Autodesk Fusion 360 part; units mm, degrees
(part 6 of 7)
sketch "Join stock profile (1) (6)" plane through (0, 0, 33.1) normal (0, 0, 1) x (1, 0, 0) in component "rear left public turning fork"
  line L0 (-286, 258) -> (-279, 258)
  line L1 (-279, 258) -> (-279, 272)
  line L2 (-279, 272) -> (-286, 272)
  line L3 (-286, 272) -> (-286, 258)
extrude "Join 3'''''" add sketch "Join stock profile (1) (6)" along normal blind 39 bodies 228 in component "rear left public turning fork"
ref_plane "WorkPlane4" through (0, 0, 33.1) normal (0, 0, 1) x (1, 0, 0) in component "rear left public turning fork"
sketch "Join stock profile (2) (7)" plane through (0, 0, 33.1) normal (0, 0, 1) x (1, 0, 0) in component "rear left public turning fork"
  line L0 (-251, 258) -> (-244, 258)
  line L1 (-244, 258) -> (-244, 272)
  line L2 (-244, 272) -> (-251, 272)
  line L3 (-251, 272) -> (-251, 258)
extrude "Join 4'''''" add sketch "Join stock profile (2) (7)" along normal blind 39 bodies 228 in component "rear left public turning fork"
ref_plane "WorkPlane5" through (-287, 0, 0) normal (1, 0, 0) x (0, 1, 0) in component "rear left public turning fork"
sketch "Cut stock profile (62)" plane through (-287, 0, 0) normal (1, 0, 0) x (0, 0, -1) in component "rear left public turning fork"
  circle A0 centre (-38.1, 265) radius 5
ref_plane "WorkPlane1" through (-286, 0, 0) normal (1, 0, 0) x (0, 1, 0) in component "rear left public wheel axle"
sketch "New stock profile (103)" plane through (-286, 0, 0) normal (1, 0, 0) x (0, 0, -1) in component "rear left public wheel axle"
  circle A0 centre (-38.1, 265) radius 5
extrude "New 1''''''''''''''''''''''''''''''''''''''''''''''''''''''''''''''''''''''''''''''''''''''''''''''''''''''" add sketch "New stock profile (103)" along normal blind 42 separate body makes body 229 in component "rear left public wheel axle"
ref_plane "WorkPlane1" through (10, 0, 0) normal (1, 0, 0) x (0, 1, 0) in component "rear left public wheel"
sketch "New stock profile (104)" plane through (10, 0, 0) normal (1, 0, 0) x (0, 0, -1) in component "rear left public wheel"
  circle A0 centre (-10, 0) radius 38.1
  circle A1 centre (-10, 0) radius 5
extrude "New 1'''''''''''''''''''''''''''''''''''''''''''''''''''''''''''''''''''''''''''''''''''''''''''''''''''''''" add sketch "New stock profile (104)" against normal blind 26 separate body makes body 230 in component "rear left public wheel"
ref_plane "WorkPlane1" through (0, 0, 3.1) normal (0, 0, 1) x (1, 0, 0) in component "rear right public drive housing"
sketch "New stock profile (105)" plane through (0, 0, 3.1) normal (0, 0, 1) x (1, 0, 0) in component "rear right public drive housing"
  circle A0 centre (3, 3) radius 30
  circle A1 centre (3, 3) radius 20
extrude "New 1''''''''''''''''''''''''''''''''''''''''''''''''''''''''''''''''''''''''''''''''''''''''''''''''''''''''" add sketch "New stock profile (105)" along normal blind 48 separate body makes body 231 in component "rear right public drive housing"
ref_plane "WorkPlane2" through (0, 0, -1.9) normal (0, 0, 1) x (1, 0, 0) in component "rear right public drive housing"
sketch "Join stock profile (39)" plane through (0, 0, -1.9) normal (0, 0, 1) x (1, 0, 0) in component "rear right public drive housing"
  line L0 (15, 15) -> (29, 15)
  line L1 (29, 15) -> (29, 29)
  line L2 (29, 29) -> (15, 29)
  line L3 (15, 29) -> (15, 15)
extrude "Join 2''''''''''''''''''''''''''''''''''''''" add sketch "Join stock profile (39)" along normal blind 53 bodies 231 in component "rear right public drive housing"
ref_plane "WorkPlane3" through (0, 0, -4.4362) normal (0, 0, 1) x (1, 0, 0) in component "rear right public drive housing"
sketch "Join stock profile (1) (7)" plane through (0, 0, -4.4362) normal (0, 0, 1) x (1, 0, 0) in component "rear right public drive housing"
  line L0 (22, -33) -> (29, -33)
  line L1 (29, -33) -> (29, 28)
  line L2 (29, 28) -> (22, 28)
  line L3 (22, 28) -> (22, -33)
extrude "Join 3''''''" add sketch "Join stock profile (1) (7)" along normal blind 4.2863 bodies 231 in component "rear right public drive housing"
ref_plane "WorkPlane4" through (0, 0, -4.4362) normal (0, 0, 1) x (1, 0, 0) in component "rear right public drive housing"
sketch "Join stock profile (2) (8)" plane through (0, 0, -4.4362) normal (0, 0, 1) x (1, 0, 0) in component "rear right public drive housing"
  line L0 (25, -34) -> (90.7, -34)
  line L1 (90.7, -34) -> (90.7, -23)
  line L2 (90.7, -23) -> (25, -23)
  line L3 (25, -23) -> (25, -34)
extrude "Join 4''''''" add sketch "Join stock profile (2) (8)" along normal blind 4.2863 bodies 231 in component "rear right public drive housing"
ref_plane "WorkPlane5" through (0, 0, -4.4362) normal (0, 0, 1) x (1, 0, 0) in component "rear right public drive housing"
sketch "Join stock profile (3) (5)" plane through (0, 0, -4.4362) normal (0, 0, 1) x (1, 0, 0) in component "rear right public drive housing"
  line L0 (-33, 22) -> (28, 22)
  line L1 (28, 22) -> (28, 29)
  line L2 (28, 29) -> (-33, 29)
  line L3 (-33, 29) -> (-33, 22)
extrude "Join 5'''" add sketch "Join stock profile (3) (5)" along normal blind 4.2863 bodies 231 in component "rear right public drive housing"
ref_plane "WorkPlane6" through (0, 0, -4.4362) normal (0, 0, 1) x (1, 0, 0) in component "rear right public drive housing"
sketch "Join stock profile (4) (5)" plane through (0, 0, -4.4362) normal (0, 0, 1) x (1, 0, 0) in component "rear right public drive housing"
  line L0 (-34, 25) -> (-23, 25)
  line L1 (-23, 25) -> (-23, 90.7)
  line L2 (-23, 90.7) -> (-34, 90.7)
  line L3 (-34, 90.7) -> (-34, 25)
extrude "Join 6'''" add sketch "Join stock profile (4) (5)" along normal blind 4.2863 bodies 231 in component "rear right public drive housing"
ref_plane "WorkPlane7" through (0, 0, -4.4463) normal (0, 0, 1) x (1, 0, 0) in component "rear right public drive housing"
sketch "Cut stock profile (63)" plane through (0, 0, -4.4463) normal (0, 0, 1) x (1, 0, 0) in component "rear right public drive housing"
  circle A0 centre (60.15, -28.75) radius 2.5
extrude "Cut 7''''''''" cut sketch "Cut stock profile (63)" along normal blind 4.3063 bodies 231 in component "rear right public drive housing"
extrude "Extrude4''''''''''''''" [no effect] in component "rear right tab 1-1 socket screw"
ref_plane "WorkPlane8" through (0, 0, -4.4463) normal (0, 0, 1) x (1, 0, 0) in component "rear right public drive housing"
sketch "Cut stock profile (1) (17)" plane through (0, 0, -4.4463) normal (0, 0, 1) x (1, 0, 0) in component "rear right public drive housing"
  circle A0 centre (85.55, -28.75) radius 2.5
extrude "Cut 8'''" cut sketch "Cut stock profile (1) (17)" along normal blind 4.3063 bodies 231 in component "rear right public drive housing"
extrude "Extrude4'''''''''''''''" [no effect] in component "rear right tab 1-2 socket screw"
ref_plane "WorkPlane9" through (0, 0, -4.4463) normal (0, 0, 1) x (1, 0, 0) in component "rear right public drive housing"
sketch "Cut stock profile (2) (17)" plane through (0, 0, -4.4463) normal (0, 0, 1) x (1, 0, 0) in component "rear right public drive housing"
  circle A0 centre (-28.75, 60.15) radius 2.5
extrude "Cut 9'''" cut sketch "Cut stock profile (2) (17)" along normal blind 4.3063 bodies 231 in component "rear right public drive housing"
extrude "Extrude4''''''''''''''''" [no effect] in component "rear right tab 2-1 socket screw"
ref_plane "WorkPlane10" through (0, 0, -4.4463) normal (0, 0, 1) x (1, 0, 0) in component "rear right public drive housing"
sketch "Cut stock profile (3) (15)" plane through (0, 0, -4.4463) normal (0, 0, 1) x (1, 0, 0) in component "rear right public drive housing"
  circle A0 centre (-28.75, 85.55) radius 2.5
extrude "Cut 10'''" cut sketch "Cut stock profile (3) (15)" along normal blind 4.3063 bodies 231 in component "rear right public drive housing"
extrude "Extrude4'''''''''''''''''" [no effect] in component "rear right tab 2-2 socket screw"
ref_plane "WorkPlane11" through (0, 0, 50.65) normal (0, 0, 1) x (1, 0, 0) in component "rear right public drive housing"
sketch "Join stock profile (5) (5)" plane through (0, 0, 50.65) normal (0, 0, 1) x (1, 0, 0) in component "rear right public drive housing"
  line L0 (22, -33) -> (29, -33)
  line L1 (29, -33) -> (29, 28)
  line L2 (29, 28) -> (22, 28)
  line L3 (22, 28) -> (22, -33)
extrude "Join 11'''" add sketch "Join stock profile (5) (5)" along normal blind 3.6625 bodies 231 in component "rear right public drive housing"
ref_plane "WorkPlane12" through (0, 0, 50.65) normal (0, 0, 1) x (1, 0, 0) in component "rear right public drive housing"
sketch "Join stock profile (6) (5)" plane through (0, 0, 50.65) normal (0, 0, 1) x (1, 0, 0) in component "rear right public drive housing"
  line L0 (25, -34) -> (90.7, -34)
  line L1 (90.7, -34) -> (90.7, -23)
  line L2 (90.7, -23) -> (25, -23)
  line L3 (25, -23) -> (25, -34)
extrude "Join 12'''" add sketch "Join stock profile (6) (5)" along normal blind 3.6625 bodies 231 in component "rear right public drive housing"
ref_plane "WorkPlane13" through (0, 0, 50.65) normal (0, 0, 1) x (1, 0, 0) in component "rear right public drive housing"
sketch "Join stock profile (7) (5)" plane through (0, 0, 50.65) normal (0, 0, 1) x (1, 0, 0) in component "rear right public drive housing"
  line L0 (-33, 22) -> (28, 22)
  line L1 (28, 22) -> (28, 29)
  line L2 (28, 29) -> (-33, 29)
  line L3 (-33, 29) -> (-33, 22)
extrude "Join 13'''" add sketch "Join stock profile (7) (5)" along normal blind 3.6625 bodies 231 in component "rear right public drive housing"
ref_plane "WorkPlane14" through (0, 0, 50.65) normal (0, 0, 1) x (1, 0, 0) in component "rear right public drive housing"
sketch "Join stock profile (8) (5)" plane through (0, 0, 50.65) normal (0, 0, 1) x (1, 0, 0) in component "rear right public drive housing"
  line L0 (-34, 25) -> (-23, 25)
  line L1 (-23, 25) -> (-23, 90.7)
  line L2 (-23, 90.7) -> (-34, 90.7)
  line L3 (-34, 90.7) -> (-34, 25)
extrude "Join 14'''" add sketch "Join stock profile (8) (5)" along normal blind 3.6625 bodies 231 in component "rear right public drive housing"
ref_plane "WorkPlane15" through (0, 0, 50.64) normal (0, 0, 1) x (1, 0, 0) in component "rear right public drive housing"
sketch "Cut stock profile (4) (15)" plane through (0, 0, 50.64) normal (0, 0, 1) x (1, 0, 0) in component "rear right public drive housing"
  circle A0 centre (60.15, -28.75) radius 2.5
extrude "Cut 15'''" cut sketch "Cut stock profile (4) (15)" along normal blind 3.6825 bodies 231 in component "rear right public drive housing"
extrude "Extrude5''''''''''''''" [no effect] in component "rear right tab 1-1 socket screw"
extrude "Extrude2'''''''''''''''" [no effect] in component "rear right tab 1-1 locknut"
ref_plane "WorkPlane16" through (0, 0, 50.64) normal (0, 0, 1) x (1, 0, 0) in component "rear right public drive housing"
sketch "Cut stock profile (5) (13)" plane through (0, 0, 50.64) normal (0, 0, 1) x (1, 0, 0) in component "rear right public drive housing"
  circle A0 centre (85.55, -28.75) radius 2.5
extrude "Cut 16'''" cut sketch "Cut stock profile (5) (13)" along normal blind 3.6825 bodies 231 in component "rear right public drive housing"
extrude "Extrude5'''''''''''''''" [no effect] in component "rear right tab 1-2 socket screw"
extrude "Extrude2''''''''''''''''" [no effect] in component "rear right tab 1-2 locknut"
ref_plane "WorkPlane17" through (0, 0, 50.64) normal (0, 0, 1) x (1, 0, 0) in component "rear right public drive housing"
sketch "Cut stock profile (6) (5)" plane through (0, 0, 50.64) normal (0, 0, 1) x (1, 0, 0) in component "rear right public drive housing"
  circle A0 centre (-28.75, 60.15) radius 2.5
extrude "Cut 17'''" cut sketch "Cut stock profile (6) (5)" along normal blind 3.6825 bodies 231 in component "rear right public drive housing"
extrude "Extrude5''''''''''''''''" [no effect] in component "rear right tab 2-1 socket screw"
extrude "Extrude2'''''''''''''''''" [no effect] in component "rear right tab 2-1 locknut"
ref_plane "WorkPlane18" through (0, 0, 50.64) normal (0, 0, 1) x (1, 0, 0) in component "rear right public drive housing"
sketch "Cut stock profile (7) (5)" plane through (0, 0, 50.64) normal (0, 0, 1) x (1, 0, 0) in component "rear right public drive housing"
  circle A0 centre (-28.75, 85.55) radius 2.5
extrude "Cut 18'''" cut sketch "Cut stock profile (7) (5)" along normal blind 3.6825 bodies 231 in component "rear right public drive housing"
extrude "Extrude5'''''''''''''''''" [no effect] in component "rear right tab 2-2 socket screw"
extrude "Extrude2''''''''''''''''''" [no effect] in component "rear right tab 2-2 locknut"
ref_plane "WorkPlane1" through (0, 0, 6.1) normal (0, 0, 1) x (1, 0, 0) in component "rear right public motor reserve"
sketch "New stock profile (106)" plane through (0, 0, 6.1) normal (0, 0, 1) x (1, 0, 0) in component "rear right public motor reserve"
  circle A0 centre (19, 19) radius 19
extrude "New 1'''''''''''''''''''''''''''''''''''''''''''''''''''''''''''''''''''''''''''''''''''''''''''''''''''''''''" add sketch "New stock profile (106)" along normal blind 50.36 separate body makes body 232 in component "rear right public motor reserve"
ref_plane "WorkPlane1" through (0, 0, 68.1) normal (0, 0, 1) x (1, 0, 0) in component "rear right public turning fork"
sketch "New stock profile (107)" plane through (0, 0, 68.1) normal (0, 0, 1) x (1, 0, 0) in component "rear right public turning fork"
  circle A0 centre (-265, -265) radius 19.95
extrude "New 1''''''''''''''''''''''''''''''''''''''''''''''''''''''''''''''''''''''''''''''''''''''''''''''''''''''''''" add sketch "New stock profile (107)" along normal blind 23 separate body makes body 233 in component "rear right public turning fork"
ref_plane "WorkPlane2" through (0, 0, 68.1) normal (0, 0, 1) x (1, 0, 0) in component "rear right public turning fork"
sketch "Join stock profile (40)" plane through (0, 0, 68.1) normal (0, 0, 1) x (1, 0, 0) in component "rear right public turning fork"
  circle A0 centre (-265, -265) radius 25.5
extrude "Join 2'''''''''''''''''''''''''''''''''''''''" add sketch "Join stock profile (40)" along normal blind 5 bodies 233 in component "rear right public turning fork"
ref_plane "WorkPlane3" through (0, 0, 33.1) normal (0, 0, 1) x (1, 0, 0) in component "rear right public turning fork"
sketch "Join stock profile (1) (8)" plane through (0, 0, 33.1) normal (0, 0, 1) x (1, 0, 0) in component "rear right public turning fork"
  line L0 (-272, -286) -> (-258, -286)
  line L1 (-258, -286) -> (-258, -279)
  line L2 (-258, -279) -> (-272, -279)
  line L3 (-272, -279) -> (-272, -286)
extrude "Join 3'''''''" add sketch "Join stock profile (1) (8)" along normal blind 39 bodies 233 in component "rear right public turning fork"
ref_plane "WorkPlane4" through (0, 0, 33.1) normal (0, 0, 1) x (1, 0, 0) in component "rear right public turning fork"
sketch "Join stock profile (2) (9)" plane through (0, 0, 33.1) normal (0, 0, 1) x (1, 0, 0) in component "rear right public turning fork"
  line L0 (-272, -251) -> (-258, -251)
  line L1 (-258, -251) -> (-258, -244)
  line L2 (-258, -244) -> (-272, -244)
  line L3 (-272, -244) -> (-272, -251)
extrude "Join 4'''''''" add sketch "Join stock profile (2) (9)" along normal blind 39 bodies 233 in component "rear right public turning fork"
ref_plane "WorkPlane5" through (0, -287, 0) normal (0, 1, 0) x (0, 0, 1) in component "rear right public turning fork"
sketch "Cut stock profile (64)" plane through (0, -287, 0) normal (0, 1, 0) x (1, 0, 0) in component "rear right public turning fork"
  circle A0 centre (-265, -38.1) radius 5
ref_plane "WorkPlane1" through (0, -286, 0) normal (0, 1, 0) x (0, 0, 1) in component "rear right public wheel axle"
sketch "New stock profile (108)" plane through (0, -286, 0) normal (0, 1, 0) x (1, 0, 0) in component "rear right public wheel axle"
  circle A0 centre (-265, -38.1) radius 5
extrude "New 1'''''''''''''''''''''''''''''''''''''''''''''''''''''''''''''''''''''''''''''''''''''''''''''''''''''''''''" add sketch "New stock profile (108)" along normal blind 42 separate body makes body 234 in component "rear right public wheel axle"
ref_plane "WorkPlane1" through (0, 0, 3) normal (0, 0, 1) x (1, 0, 0) in component "rear right public wheel"
sketch "New stock profile (109)" plane through (0, 0, 3) normal (0, 0, 1) x (1, 0, 0) in component "rear right public wheel"
  circle A0 centre (-3, 0) radius 38.1
  circle A1 centre (-3, 0) radius 5
extrude "New 1''''''''''''''''''''''''''''''''''''''''''''''''''''''''''''''''''''''''''''''''''''''''''''''''''''''''''''" add sketch "New stock profile (109)" along normal blind 26 separate body makes body 235 in component "rear right public wheel"
ref_plane "WorkPlane1" through (0, 0, 38.1) normal (0, 0, 1) x (1, 0, 0)
sketch "Module joint datum" plane through (0, 0, 38.1) normal (0, 0, 1) x (1, 0, 0)
  point P0 (265, 265)
ref_plane "WorkPlane2" through (0, 0, 38.1) normal (0, 0, 1) x (1, 0, 0)
sketch "Module joint datum (1)" plane through (0, 0, 38.1) normal (0, 0, 1) x (1, 0, 0)
  point P0 (265, -265)
ref_plane "WorkPlane3" through (0, 0, 38.1) normal (0, 0, 1) x (1, 0, 0)
sketch "Module joint datum (2)" plane through (0, 0, 38.1) normal (0, 0, 1) x (1, 0, 0)
  point P0 (-265, 265)
ref_plane "WorkPlane4" through (0, 0, 38.1) normal (0, 0, 1) x (1, 0, 0)
sketch "Module joint datum (3)" plane through (0, 0, 38.1) normal (0, 0, 1) x (1, 0, 0)
  point P0 (-265, -265)
ref_plane "WorkPlane7" through (0, -22.225, 0) normal (0, 1, 0) x (0, 0, 1) in component "rear perimeter tube"
sketch "Cut stock profile (5) (14)" plane through (0, -22.225, 0) normal (0, 1, 0) x (1, 0, 0) in component "rear perimeter tube"
  line L0 (9.525, 1) -> (-9.525, 1)
  line L1 (-9.525, 1) -> (-9.525, -630.2)
  line L2 (-9.525, -630.2) -> (9.525, -630.2)
  line L3 (9.525, -630.2) -> (9.525, 1)
extrude "Cut 1" cut sketch "Cut stock profile (5) (14)" along normal blind 44.45 bodies 127 in component "rear perimeter tube"
ref_plane "WorkPlane8" through (-9.2, 0, 0) normal (1, 0, 0) x (0, 1, 0) in component "rear perimeter tube"
sketch "Cut stock profile (6) (6)" plane through (-9.2, 0, 0) normal (1, 0, 0) x (0, 0, -1) in component "rear perimeter tube"
  circle A0 centre (-509.75, -5.3) radius 6.55
extrude "Cut 1 (1)" cut sketch "Cut stock profile (6) (6)" against normal blind 4.5 bodies 127 in component "rear perimeter tube"
ref_plane "WorkPlane9" through (-9.2, 0, 0) normal (1, 0, 0) x (0, 1, 0) in component "rear perimeter tube"
sketch "Cut stock profile (7) (6)" plane through (-9.2, 0, 0) normal (1, 0, 0) x (0, 0, -1) in component "rear perimeter tube"
  circle A0 centre (-509.75, 15.7) radius 6.55
extrude "Cut 1 (2)" cut sketch "Cut stock profile (7) (6)" against normal blind 4.5 bodies 127 in component "rear perimeter tube"
ref_plane "WorkPlane10" through (-9.2, 0, 0) normal (1, 0, 0) x (0, 1, 0) in component "rear perimeter tube"
sketch "Cut stock profile (8) (2)" plane through (-9.2, 0, 0) normal (1, 0, 0) x (0, 0, -1) in component "rear perimeter tube"
  circle A0 centre (-119.45, -5.3) radius 6.55
extrude "Cut 1 (3)" cut sketch "Cut stock profile (8) (2)" against normal blind 4.5 bodies 127 in component "rear perimeter tube"
ref_plane "WorkPlane11" through (-9.2, 0, 0) normal (1, 0, 0) x (0, 1, 0) in component "rear perimeter tube"
sketch "Cut stock profile (9) (2)" plane through (-9.2, 0, 0) normal (1, 0, 0) x (0, 0, -1) in component "rear perimeter tube"
  circle A0 centre (-119.45, 15.7) radius 6.55
extrude "Cut 1 (4)" cut sketch "Cut stock profile (9) (2)" against normal blind 4.5 bodies 127 in component "rear perimeter tube"
ref_plane "WorkPlane7" through (9.2, 0, 0) normal (1, 0, 0) x (0, 1, 0) in component "right perimeter tube"
sketch "Cut stock profile (5) (15)" plane through (9.2, 0, 0) normal (1, 0, 0) x (0, 0, -1) in component "right perimeter tube"
  circle A0 centre (-535.15, -5.3) radius 6.55
extrude "Cut 1'" cut sketch "Cut stock profile (5) (15)" along normal blind 4.5 bodies 128 in component "right perimeter tube"
ref_plane "WorkPlane8" through (9.2, 0, 0) normal (1, 0, 0) x (0, 1, 0) in component "right perimeter tube"
sketch "Cut stock profile (6) (7)" plane through (9.2, 0, 0) normal (1, 0, 0) x (0, 0, -1) in component "right perimeter tube"
  circle A0 centre (-535.15, 15.7) radius 6.55
extrude "Cut 1 (1)'" cut sketch "Cut stock profile (6) (7)" along normal blind 4.5 bodies 128 in component "right perimeter tube"
ref_plane "WorkPlane9" through (9.2, 0, 0) normal (1, 0, 0) x (0, 1, 0) in component "right perimeter tube"
sketch "Cut stock profile (7) (7)" plane through (9.2, 0, 0) normal (1, 0, 0) x (0, 0, -1) in component "right perimeter tube"
  circle A0 centre (-144.85, -5.3) radius 6.55
extrude "Cut 1 (2)'" cut sketch "Cut stock profile (7) (7)" along normal blind 4.5 bodies 128 in component "right perimeter tube"
ref_plane "WorkPlane10" through (9.2, 0, 0) normal (1, 0, 0) x (0, 1, 0) in component "right perimeter tube"
sketch "Cut stock profile (8) (3)" plane through (9.2, 0, 0) normal (1, 0, 0) x (0, 0, -1) in component "right perimeter tube"
  circle A0 centre (-144.85, 15.7) radius 6.55
extrude "Cut 1 (3)'" cut sketch "Cut stock profile (8) (3)" along normal blind 4.5 bodies 128 in component "right perimeter tube"
ref_plane "WorkPlane5" through (9.2, 0, 0) normal (1, 0, 0) x (0, 1, 0) in component "right front return"
sketch "Cut stock profile (3) (16)" plane through (9.2, 0, 0) normal (1, 0, 0) x (0, 0, -1) in component "right front return"
  circle A0 centre (-119.45, -5.3) radius 6.55
extrude "Cut 1''" cut sketch "Cut stock profile (3) (16)" along normal blind 4.5 bodies 129 in component "right front return"
ref_plane "WorkPlane6" through (9.2, 0, 0) normal (1, 0, 0) x (0, 1, 0) in component "right front return"
sketch "Cut stock profile (4) (16)" plane through (9.2, 0, 0) normal (1, 0, 0) x (0, 0, -1) in component "right front return"
  circle A0 centre (-119.45, 15.7) radius 6.55
extrude "Cut 1 (1)''" cut sketch "Cut stock profile (4) (16)" along normal blind 4.5 bodies 129 in component "right front return"
ref_plane "WorkPlane3" through (0, -14.4752, 0) normal (0, 1, 0) x (0, 0, 1) in component "right floor sill"
sketch "Cut stock profile (1) (18)" plane through (0, -14.4752, 0) normal (0, 1, 0) x (1, 0, 0) in component "right floor sill"
  line L0 (4.0498, 1) -> (4.0498, -481)
  line L1 (4.0498, -481) -> (19.9502, -481)
  line L2 (19.9502, -481) -> (19.9502, 1)
  line L3 (19.9502, 1) -> (4.0498, 1)
extrude "Cut 1'''" cut sketch "Cut stock profile (1) (18)" along normal blind 15.9004 bodies 130 in component "right floor sill"
ref_plane "WorkPlane7" through (-9.2, 0, 0) normal (1, 0, 0) x (0, 1, 0) in component "left perimeter tube"
sketch "Cut stock profile (5) (16)" plane through (-9.2, 0, 0) normal (1, 0, 0) x (0, 0, -1) in component "left perimeter tube"
  circle A0 centre (-535.15, -5.3) radius 6.55
extrude "Cut 1''''" cut sketch "Cut stock profile (5) (16)" against normal blind 4.5 bodies 133 in component "left perimeter tube"
ref_plane "WorkPlane8" through (-9.2, 0, 0) normal (1, 0, 0) x (0, 1, 0) in component "left perimeter tube"
sketch "Cut stock profile (6) (8)" plane through (-9.2, 0, 0) normal (1, 0, 0) x (0, 0, -1) in component "left perimeter tube"
  circle A0 centre (-535.15, 15.7) radius 6.55
extrude "Cut 1 (1)'''" cut sketch "Cut stock profile (6) (8)" against normal blind 4.5 bodies 133 in component "left perimeter tube"
ref_plane "WorkPlane9" through (-9.2, 0, 0) normal (1, 0, 0) x (0, 1, 0) in component "left perimeter tube"
sketch "Cut stock profile (7) (8)" plane through (-9.2, 0, 0) normal (1, 0, 0) x (0, 0, -1) in component "left perimeter tube"
  circle A0 centre (-144.85, -5.3) radius 6.55
extrude "Cut 1 (2)''" cut sketch "Cut stock profile (7) (8)" against normal blind 4.5 bodies 133 in component "left perimeter tube"
ref_plane "WorkPlane10" through (-9.2, 0, 0) normal (1, 0, 0) x (0, 1, 0) in component "left perimeter tube"
sketch "Cut stock profile (8) (4)" plane through (-9.2, 0, 0) normal (1, 0, 0) x (0, 0, -1) in component "left perimeter tube"
  circle A0 centre (-144.85, 15.7) radius 6.55
extrude "Cut 1 (3)''" cut sketch "Cut stock profile (8) (4)" against normal blind 4.5 bodies 133 in component "left perimeter tube"
ref_plane "WorkPlane5" through (9.2, 0, 0) normal (1, 0, 0) x (0, 1, 0) in component "left front return"
sketch "Cut stock profile (3) (17)" plane through (9.2, 0, 0) normal (1, 0, 0) x (0, 0, -1) in component "left front return"
  circle A0 centre (-45.15, -5.3) radius 6.55
extrude "Cut 1'''''" cut sketch "Cut stock profile (3) (17)" along normal blind 4.5 bodies 134 in component "left front return"
ref_plane "WorkPlane6" through (9.2, 0, 0) normal (1, 0, 0) x (0, 1, 0) in component "left front return"
sketch "Cut stock profile (4) (17)" plane through (9.2, 0, 0) normal (1, 0, 0) x (0, 0, -1) in component "left front return"
  circle A0 centre (-45.15, 15.7) radius 6.55
extrude "Cut 1 (1)''''" cut sketch "Cut stock profile (4) (17)" along normal blind 4.5 bodies 134 in component "left front return"
ref_plane "WorkPlane3" through (0, -14.4752, 0) normal (0, 1, 0) x (0, 0, 1) in component "left floor sill"
sketch "Cut stock profile (1) (19)" plane through (0, -14.4752, 0) normal (0, 1, 0) x (1, 0, 0) in component "left floor sill"
  line L0 (-19.9502, 1) -> (-19.9502, -481)
  line L1 (-19.9502, -481) -> (-4.0498, -481)
  line L2 (-4.0498, -481) -> (-4.0498, 1)
  line L3 (-4.0498, 1) -> (-19.9502, 1)
extrude "Cut 1''''''" cut sketch "Cut stock profile (1) (19)" along normal blind 15.9004 bodies 135 in component "left floor sill"
ref_plane "WorkPlane6" through (0, 287, 0) normal (0, 1, 0) x (0, 0, 1) in component "front left public turning fork"
sketch "Cut stock profile (1) (20)" plane through (0, 287, 0) normal (0, 1, 0) x (1, 0, 0) in component "front left public turning fork"
  circle A0 centre (265, -38.1) radius 5
extrude "Cut 1'''''''" cut sketch "Cut stock profile (1) (20)" against normal blind 44 bodies 218 in component "front left public turning fork"
ref_plane "WorkPlane6" through (287, 0, 0) normal (1, 0, 0) x (0, 1, 0) in component "front right public turning fork"
sketch "Cut stock profile (1) (21)" plane through (287, 0, 0) normal (1, 0, 0) x (0, 0, -1) in component "front right public turning fork"
  circle A0 centre (-38.1, -265) radius 5
extrude "Cut 1''''''''" cut sketch "Cut stock profile (1) (21)" against normal blind 44 bodies 223 in component "front right public turning fork"
ref_plane "WorkPlane6" through (-287, 0, 0) normal (1, 0, 0) x (0, 1, 0) in component "rear left public turning fork"
sketch "Cut stock profile (1) (22)" plane through (-287, 0, 0) normal (1, 0, 0) x (0, 0, -1) in component "rear left public turning fork"
  circle A0 centre (-38.1, 265) radius 5
extrude "Cut 1'''''''''" cut sketch "Cut stock profile (1) (22)" along normal blind 44 bodies 228 in component "rear left public turning fork"
ref_plane "WorkPlane6" through (0, -287, 0) normal (0, 1, 0) x (0, 0, 1) in component "rear right public turning fork"
sketch "Cut stock profile (1) (23)" plane through (0, -287, 0) normal (0, 1, 0) x (1, 0, 0) in component "rear right public turning fork"
  circle A0 centre (-265, -38.1) radius 5
extrude "Cut 1''''''''''" cut sketch "Cut stock profile (1) (23)" along normal blind 44 bodies 233 in component "rear right public turning fork"
ref_plane "WorkPlane1" through (0, 416, 0) normal (0, 1, 0) x (0, 0, 1) in component "left white 1780 digit 1"
sketch "1780 ink outline 1" plane through (0, 416, 0) normal (0, 1, 0) x (1, 0, 0) in component "left white 1780 digit 1"
  line L0 (82.5, -138) -> (82.5, -152)
  line L1 (82.5, -152) -> (72.5, -158)
  line L2 (72.5, -158) -> (59.5, -158)
  line L3 (59.5, -158) -> (59.5, -58)
  line L4 (59.5, -58) -> (72.5, -58)
  line L5 (72.5, -58) -> (72.5, -143)
  line L6 (72.5, -143) -> (82.5, -138)
extrude "White print relief" add sketch "1780 ink outline 1" along normal blind 0.12 separate body makes body 236 in component "left white 1780 digit 1"
ref_plane "WorkPlane1" through (0, 416, 0) normal (0, 1, 0) x (0, 0, 1) in component "left white 1780 digit 7"
sketch "1780 ink outline 7" plane through (0, 416, 0) normal (0, 1, 0) x (1, 0, 0) in component "left white 1780 digit 7"
  line L0 (54.5, -158) -> (12.5, -158)
  line L1 (12.5, -158) -> (12.5, -145)
  line L2 (12.5, -145) -> (35.5, -58)
  line L3 (35.5, -58) -> (49.3, -58)
  line L4 (49.3, -58) -> (26.3, -145)
  line L5 (26.3, -145) -> (54.5, -145)
  line L6 (54.5, -145) -> (54.5, -158)
extrude "White print relief'" add sketch "1780 ink outline 7" along normal blind 0.12 separate body makes body 237 in component "left white 1780 digit 7"
ref_plane "WorkPlane1" through (0, 416, 0) normal (0, 1, 0) x (0, 0, 1) in component "left white 1780 digit 8"
sketch "1780 ink outline 8" plane through (0, 416, 0) normal (0, 1, 0) x (1, 0, 0) in component "left white 1780 digit 8"
  line L0 (2.5, -58) -> (-29.5, -58)
  line L1 (-29.5, -58) -> (-34.5, -63)
  line L2 (-34.5, -63) -> (-34.5, -153)
  line L3 (-34.5, -153) -> (-29.5, -158)
  line L4 (-29.5, -158) -> (2.5, -158)
  line L5 (2.5, -158) -> (7.5, -153)
  line L6 (7.5, -153) -> (7.5, -63)
  line L7 (7.5, -63) -> (2.5, -58)
  line L8 (-8, -71) -> (-19, -71)
  line L9 (-19, -71) -> (-21.5, -73.5)
  line L10 (-21.5, -73.5) -> (-21.5, -99)
  line L11 (-21.5, -99) -> (-19, -101.5)
  line L12 (-19, -101.5) -> (-8, -101.5)
  line L13 (-8, -101.5) -> (-5.5, -99)
  line L14 (-5.5, -99) -> (-5.5, -73.5)
  line L15 (-5.5, -73.5) -> (-8, -71)
  line L16 (-8, -114.5) -> (-19, -114.5)
  line L17 (-19, -114.5) -> (-21.5, -117)
  line L18 (-21.5, -117) -> (-21.5, -142.5)
  line L19 (-21.5, -142.5) -> (-19, -145)
  line L20 (-19, -145) -> (-8, -145)
  line L21 (-8, -145) -> (-5.5, -142.5)
  line L22 (-5.5, -142.5) -> (-5.5, -117)
  line L23 (-5.5, -117) -> (-8, -114.5)
extrude "White print relief''" add sketch "1780 ink outline 8" along normal blind 0.12 separate body makes body 238 in component "left white 1780 digit 8"
ref_plane "WorkPlane1" through (0, 416, 0) normal (0, 1, 0) x (0, 0, 1) in component "left white 1780 digit 0"
sketch "1780 ink outline 0" plane through (0, 416, 0) normal (0, 1, 0) x (1, 0, 0) in component "left white 1780 digit 0"
  line L0 (-44.5, -58) -> (-77.5, -58)
  line L1 (-77.5, -58) -> (-82.5, -63)
  line L2 (-82.5, -63) -> (-82.5, -153)
  line L3 (-82.5, -153) -> (-77.5, -158)
  line L4 (-77.5, -158) -> (-44.5, -158)
  line L5 (-44.5, -158) -> (-39.5, -153)
  line L6 (-39.5, -153) -> (-39.5, -63)
  line L7 (-39.5, -63) -> (-44.5, -58)
  line L8 (-55.5, -71) -> (-66.5, -71)
  line L9 (-66.5, -71) -> (-69.5, -74)
  line L10 (-69.5, -74) -> (-69.5, -142)
  line L11 (-69.5, -142) -> (-66.5, -145)
  line L12 (-66.5, -145) -> (-55.5, -145)
  line L13 (-55.5, -145) -> (-52.5, -142)
  line L14 (-52.5, -142) -> (-52.5, -74)
  line L15 (-52.5, -74) -> (-55.5, -71)
extrude "White print relief'''" add sketch "1780 ink outline 0" along normal blind 0.12 separate body makes body 239 in component "left white 1780 digit 0"
ref_plane "WorkPlane1" through (0, -416, 0) normal (0, 1, 0) x (0, 0, 1) in component "right white 1780 digit 1"
sketch "1780 ink outline 1 (2)" plane through (0, -416, 0) normal (0, 1, 0) x (1, 0, 0) in component "right white 1780 digit 1"
  line L0 (-82.5, -138) -> (-82.5, -152)
  line L1 (-82.5, -152) -> (-72.5, -158)
  line L2 (-72.5, -158) -> (-59.5, -158)
  line L3 (-59.5, -158) -> (-59.5, -58)
  line L4 (-59.5, -58) -> (-72.5, -58)
  line L5 (-72.5, -58) -> (-72.5, -143)
  line L6 (-72.5, -143) -> (-82.5, -138)
extrude "White print relief''''" add sketch "1780 ink outline 1 (2)" against normal blind 0.12 separate body makes body 240 in component "right white 1780 digit 1"
ref_plane "WorkPlane1" through (0, -416, 0) normal (0, 1, 0) x (0, 0, 1) in component "right white 1780 digit 7"
sketch "1780 ink outline 7 (2)" plane through (0, -416, 0) normal (0, 1, 0) x (1, 0, 0) in component "right white 1780 digit 7"
  line L0 (-54.5, -158) -> (-12.5, -158)
  line L1 (-12.5, -158) -> (-12.5, -145)
  line L2 (-12.5, -145) -> (-35.5, -58)
  line L3 (-35.5, -58) -> (-49.3, -58)
  line L4 (-49.3, -58) -> (-26.3, -145)
  line L5 (-26.3, -145) -> (-54.5, -145)
  line L6 (-54.5, -145) -> (-54.5, -158)
extrude "White print relief'''''" add sketch "1780 ink outline 7 (2)" against normal blind 0.12 separate body makes body 241 in component "right white 1780 digit 7"
ref_plane "WorkPlane1" through (0, -416, 0) normal (0, 1, 0) x (0, 0, 1) in component "right white 1780 digit 8"
sketch "1780 ink outline 8 (2)" plane through (0, -416, 0) normal (0, 1, 0) x (1, 0, 0) in component "right white 1780 digit 8"
  line L0 (-2.5, -58) -> (29.5, -58)
  line L1 (29.5, -58) -> (34.5, -63)
  line L2 (34.5, -63) -> (34.5, -153)
  line L3 (34.5, -153) -> (29.5, -158)
  line L4 (29.5, -158) -> (-2.5, -158)
  line L5 (-2.5, -158) -> (-7.5, -153)
  line L6 (-7.5, -153) -> (-7.5, -63)
  line L7 (-7.5, -63) -> (-2.5, -58)
  line L8 (8, -71) -> (19, -71)
  line L9 (19, -71) -> (21.5, -73.5)
  line L10 (21.5, -73.5) -> (21.5, -99)
  line L11 (21.5, -99) -> (19, -101.5)
  line L12 (19, -101.5) -> (8, -101.5)
  line L13 (8, -101.5) -> (5.5, -99)
  line L14 (5.5, -99) -> (5.5, -73.5)
  line L15 (5.5, -73.5) -> (8, -71)
  line L16 (8, -114.5) -> (19, -114.5)
  line L17 (19, -114.5) -> (21.5, -117)
  line L18 (21.5, -117) -> (21.5, -142.5)
  line L19 (21.5, -142.5) -> (19, -145)
  line L20 (19, -145) -> (8, -145)
  line L21 (8, -145) -> (5.5, -142.5)
  line L22 (5.5, -142.5) -> (5.5, -117)
  line L23 (5.5, -117) -> (8, -114.5)
extrude "White print relief''''''" add sketch "1780 ink outline 8 (2)" against normal blind 0.12 separate body makes body 242 in component "right white 1780 digit 8"
ref_plane "WorkPlane1" through (0, -416, 0) normal (0, 1, 0) x (0, 0, 1) in component "right white 1780 digit 0"
sketch "1780 ink outline 0 (2)" plane through (0, -416, 0) normal (0, 1, 0) x (1, 0, 0) in component "right white 1780 digit 0"
  line L0 (44.5, -58) -> (77.5, -58)
  line L1 (77.5, -58) -> (82.5, -63)
  line L2 (82.5, -63) -> (82.5, -153)
  line L3 (82.5, -153) -> (77.5, -158)
  line L4 (77.5, -158) -> (44.5, -158)
  line L5 (44.5, -158) -> (39.5, -153)
  line L6 (39.5, -153) -> (39.5, -63)
  line L7 (39.5, -63) -> (44.5, -58)
  line L8 (55.5, -71) -> (66.5, -71)
  line L9 (66.5, -71) -> (69.5, -74)
  line L10 (69.5, -74) -> (69.5, -142)
  line L11 (69.5, -142) -> (66.5, -145)
  line L12 (66.5, -145) -> (55.5, -145)
  line L13 (55.5, -145) -> (52.5, -142)
  line L14 (52.5, -142) -> (52.5, -74)
  line L15 (52.5, -74) -> (55.5, -71)
extrude "White print relief'''''''" add sketch "1780 ink outline 0 (2)" against normal blind 0.12 separate body makes body 243 in component "right white 1780 digit 0"
ref_plane "WorkPlane1" through (-416, 0, 0) normal (1, 0, 0) x (0, 1, 0) in component "rear white 1780 digit 1"
sketch "1780 ink outline 1 (3)" plane through (-416, 0, 0) normal (1, 0, 0) x (0, 0, -1) in component "rear white 1780 digit 1"
  line L0 (-138, 82.5) -> (-152, 82.5)
  line L1 (-152, 82.5) -> (-158, 72.5)
  line L2 (-158, 72.5) -> (-158, 59.5)
  line L3 (-158, 59.5) -> (-58, 59.5)
  line L4 (-58, 59.5) -> (-58, 72.5)
  line L5 (-58, 72.5) -> (-143, 72.5)
  line L6 (-143, 72.5) -> (-138, 82.5)
extrude "White print relief''''''''" add sketch "1780 ink outline 1 (3)" against normal blind 0.12 separate body makes body 244 in component "rear white 1780 digit 1"
ref_plane "WorkPlane1" through (-416, 0, 0) normal (1, 0, 0) x (0, 1, 0) in component "rear white 1780 digit 7"
sketch "1780 ink outline 7 (3)" plane through (-416, 0, 0) normal (1, 0, 0) x (0, 0, -1) in component "rear white 1780 digit 7"
  line L0 (-158, 54.5) -> (-158, 12.5)
  line L1 (-158, 12.5) -> (-145, 12.5)
  line L2 (-145, 12.5) -> (-58, 35.5)
  line L3 (-58, 35.5) -> (-58, 49.3)
  line L4 (-58, 49.3) -> (-145, 26.3)
  line L5 (-145, 26.3) -> (-145, 54.5)
  line L6 (-145, 54.5) -> (-158, 54.5)
extrude "White print relief'''''''''" add sketch "1780 ink outline 7 (3)" against normal blind 0.12 separate body makes body 245 in component "rear white 1780 digit 7"
ref_plane "WorkPlane1" through (-416, 0, 0) normal (1, 0, 0) x (0, 1, 0) in component "rear white 1780 digit 8"
sketch "1780 ink outline 8 (3)" plane through (-416, 0, 0) normal (1, 0, 0) x (0, 0, -1) in component "rear white 1780 digit 8"
  line L0 (-58, 2.5) -> (-58, -29.5)
  line L1 (-58, -29.5) -> (-63, -34.5)
  line L2 (-63, -34.5) -> (-153, -34.5)
  line L3 (-153, -34.5) -> (-158, -29.5)
  line L4 (-158, -29.5) -> (-158, 2.5)
  line L5 (-158, 2.5) -> (-153, 7.5)
  line L6 (-153, 7.5) -> (-63, 7.5)
  line L7 (-63, 7.5) -> (-58, 2.5)
  line L8 (-71, -8) -> (-71, -19)
  line L9 (-71, -19) -> (-73.5, -21.5)
  line L10 (-73.5, -21.5) -> (-99, -21.5)
  line L11 (-99, -21.5) -> (-101.5, -19)
  line L12 (-101.5, -19) -> (-101.5, -8)
  line L13 (-101.5, -8) -> (-99, -5.5)
  line L14 (-99, -5.5) -> (-73.5, -5.5)
  line L15 (-73.5, -5.5) -> (-71, -8)
  line L16 (-114.5, -8) -> (-114.5, -19)
  line L17 (-114.5, -19) -> (-117, -21.5)
  line L18 (-117, -21.5) -> (-142.5, -21.5)
  line L19 (-142.5, -21.5) -> (-145, -19)
  line L20 (-145, -19) -> (-145, -8)
  line L21 (-145, -8) -> (-142.5, -5.5)
  line L22 (-142.5, -5.5) -> (-117, -5.5)
  line L23 (-117, -5.5) -> (-114.5, -8)
extrude "White print relief''''''''''" add sketch "1780 ink outline 8 (3)" against normal blind 0.12 separate body makes body 246 in component "rear white 1780 digit 8"
ref_plane "WorkPlane1" through (-416, 0, 0) normal (1, 0, 0) x (0, 1, 0) in component "rear white 1780 digit 0"
sketch "1780 ink outline 0 (3)" plane through (-416, 0, 0) normal (1, 0, 0) x (0, 0, -1) in component "rear white 1780 digit 0"
  line L0 (-58, -44.5) -> (-58, -77.5)
  line L1 (-58, -77.5) -> (-63, -82.5)
  line L2 (-63, -82.5) -> (-153, -82.5)
  line L3 (-153, -82.5) -> (-158, -77.5)
  line L4 (-158, -77.5) -> (-158, -44.5)
  line L5 (-158, -44.5) -> (-153, -39.5)
  line L6 (-153, -39.5) -> (-63, -39.5)
  line L7 (-63, -39.5) -> (-58, -44.5)
  line L8 (-71, -55.5) -> (-71, -66.5)
  line L9 (-71, -66.5) -> (-74, -69.5)
  line L10 (-74, -69.5) -> (-142, -69.5)
  line L11 (-142, -69.5) -> (-145, -66.5)
  line L12 (-145, -66.5) -> (-145, -55.5)
  line L13 (-145, -55.5) -> (-142, -52.5)
  line L14 (-142, -52.5) -> (-74, -52.5)
  line L15 (-74, -52.5) -> (-71, -55.5)
extrude "White print relief'''''''''''" add sketch "1780 ink outline 0 (3)" against normal blind 0.12 separate body makes body 247 in component "rear white 1780 digit 0"
ref_plane "WorkPlane1" through (416, 0, 0) normal (1, 0, 0) x (0, 1, 0) in component "front white 1780 digit 1"
sketch "1780 ink outline 1 (4)" plane through (416, 0, 0) normal (1, 0, 0) x (0, 0, -1) in component "front white 1780 digit 1"
  line L0 (-138, 162.5) -> (-152, 162.5)
  line L1 (-152, 162.5) -> (-158, 172.5)
  line L2 (-158, 172.5) -> (-158, 185.5)
  line L3 (-158, 185.5) -> (-58, 185.5)
  line L4 (-58, 185.5) -> (-58, 172.5)
  line L5 (-58, 172.5) -> (-143, 172.5)
  line L6 (-143, 172.5) -> (-138, 162.5)
extrude "White print relief''''''''''''" add sketch "1780 ink outline 1 (4)" along normal blind 0.12 separate body makes body 248 in component "front white 1780 digit 1"
ref_plane "WorkPlane1" through (416, 0, 0) normal (1, 0, 0) x (0, 1, 0) in component "front white 1780 digit 7"
sketch "1780 ink outline 7 (4)" plane through (416, 0, 0) normal (1, 0, 0) x (0, 0, -1) in component "front white 1780 digit 7"
  line L0 (-158, 190.5) -> (-158, 232.5)
  line L1 (-158, 232.5) -> (-145, 232.5)
  line L2 (-145, 232.5) -> (-58, 209.5)
  line L3 (-58, 209.5) -> (-58, 195.7)
  line L4 (-58, 195.7) -> (-145, 218.7)
  line L5 (-145, 218.7) -> (-145, 190.5)
  line L6 (-145, 190.5) -> (-158, 190.5)
extrude "White print relief'''''''''''''" add sketch "1780 ink outline 7 (4)" along normal blind 0.12 separate body makes body 249 in component "front white 1780 digit 7"
ref_plane "WorkPlane1" through (416, 0, 0) normal (1, 0, 0) x (0, 1, 0) in component "front white 1780 digit 8"
sketch "1780 ink outline 8 (4)" plane through (416, 0, 0) normal (1, 0, 0) x (0, 0, -1) in component "front white 1780 digit 8"
  line L0 (-58, 242.5) -> (-58, 274.5)
  line L1 (-58, 274.5) -> (-63, 279.5)
  line L2 (-63, 279.5) -> (-153, 279.5)
  line L3 (-153, 279.5) -> (-158, 274.5)
  line L4 (-158, 274.5) -> (-158, 242.5)
  line L5 (-158, 242.5) -> (-153, 237.5)
  line L6 (-153, 237.5) -> (-63, 237.5)
  line L7 (-63, 237.5) -> (-58, 242.5)
  line L8 (-71, 253) -> (-71, 264)
  line L9 (-71, 264) -> (-73.5, 266.5)
  line L10 (-73.5, 266.5) -> (-99, 266.5)
  line L11 (-99, 266.5) -> (-101.5, 264)
  line L12 (-101.5, 264) -> (-101.5, 253)
  line L13 (-101.5, 253) -> (-99, 250.5)
  line L14 (-99, 250.5) -> (-73.5, 250.5)
  line L15 (-73.5, 250.5) -> (-71, 253)
  line L16 (-114.5, 253) -> (-114.5, 264)
  line L17 (-114.5, 264) -> (-117, 266.5)
  line L18 (-117, 266.5) -> (-142.5, 266.5)
  line L19 (-142.5, 266.5) -> (-145, 264)
  line L20 (-145, 264) -> (-145, 253)
  line L21 (-145, 253) -> (-142.5, 250.5)
  line L22 (-142.5, 250.5) -> (-117, 250.5)
  line L23 (-117, 250.5) -> (-114.5, 253)
extrude "White print relief''''''''''''''" add sketch "1780 ink outline 8 (4)" along normal blind 0.12 separate body makes body 250 in component "front white 1780 digit 8"
ref_plane "WorkPlane1" through (416, 0, 0) normal (1, 0, 0) x (0, 1, 0) in component "front white 1780 digit 0"
sketch "1780 ink outline 0 (4)" plane through (416, 0, 0) normal (1, 0, 0) x (0, 0, -1) in component "front white 1780 digit 0"
  line L0 (-58, 289.5) -> (-58, 322.5)
  line L1 (-58, 322.5) -> (-63, 327.5)
  line L2 (-63, 327.5) -> (-153, 327.5)
  line L3 (-153, 327.5) -> (-158, 322.5)
  line L4 (-158, 322.5) -> (-158, 289.5)
  line L5 (-158, 289.5) -> (-153, 284.5)
  line L6 (-153, 284.5) -> (-63, 284.5)
  line L7 (-63, 284.5) -> (-58, 289.5)
  line L8 (-71, 300.5) -> (-71, 311.5)
  line L9 (-71, 311.5) -> (-74, 314.5)
  line L10 (-74, 314.5) -> (-142, 314.5)
  line L11 (-142, 314.5) -> (-145, 311.5)
  line L12 (-145, 311.5) -> (-145, 300.5)
  line L13 (-145, 300.5) -> (-142, 297.5)
  line L14 (-142, 297.5) -> (-74, 297.5)
  line L15 (-74, 297.5) -> (-71, 300.5)
extrude "White print relief'''''''''''''''" add sketch "1780 ink outline 0 (4)" along normal blind 0.12 separate body makes body 251 in component "front white 1780 digit 0"
ref_plane "WorkPlane1" through (0, 144, 0) normal (0, 1, 0) x (0, 0, 1) in component "left intake foundation cheek"
sketch "New stock profile (110)" plane through (0, 144, 0) normal (0, 1, 0) x (1, 0, 0) in component "left intake foundation cheek"
  line L0 (141.7, -98) -> (141.7, -120)
  line L1 (141.7, -120) -> (169, -120)
  line L2 (169, -120) -> (174, -138)
  line L3 (174, -138) -> (279, -115)
  line L4 (279, -115) -> (314.6, -114.8)
  line L5 (314.6, -114.8) -> (337, -114.8)
  line L6 (337, -114.8) -> (337, -64)
  line L7 (337, -64) -> (319, -44)
  line L8 (319, -44) -> (299, -44)
  line L9 (299, -44) -> (280, -54)
  line L10 (280, -54) -> (225, -54)
  line L11 (225, -54) -> (210, -74)
  line L12 (210, -74) -> (205, -90)
  line L13 (205, -90) -> (167, -106)
  line L14 (167, -106) -> (141.7, -98)
extrude "New 1'''''''''''''''''''''''''''''''''''''''''''''''''''''''''''''''''''''''''''''''''''''''''''''''''''''''''''''" add sketch "New stock profile (110)" along normal blind 6 separate body makes body 252 in component "left intake foundation cheek"
ref_plane "WorkPlane1" through (214, 0, 0) normal (1, 0, 0) x (0, 1, 0) in component "left ramp bridge aft"
sketch "New stock profile (111)" plane through (214, 0, 0) normal (1, 0, 0) x (0, 0, -1) in component "left ramp bridge aft"
  line L0 (-44.6694, 74) -> (-19, 122)
  line L1 (-19, 122) -> (-19, 137)
  line L2 (-19, 137) -> (-67, 144)
  line L3 (-67, 144) -> (-82, 144)
  line L4 (-82, 144) -> (-28, 136)
  line L5 (-28, 136) -> (-28, 122)
  line L6 (-28, 122) -> (-48.6694, 74)
  line L7 (-48.6694, 74) -> (-44.6694, 74)
extrude "New 1''''''''''''''''''''''''''''''''''''''''''''''''''''''''''''''''''''''''''''''''''''''''''''''''''''''''''''''" add sketch "New stock profile (111)" along normal blind 8 separate body makes body 253 in component "left ramp bridge aft"
ref_plane "WorkPlane1" through (313, 0, 0) normal (1, 0, 0) x (0, 1, 0) in component "left ramp bridge forward"
sketch "New stock profile (112)" plane through (313, 0, 0) normal (1, 0, 0) x (0, 0, -1) in component "left ramp bridge forward"
  line L0 (-18.3226, 74) -> (-57, 144)
  line L1 (-57, 144) -> (-72, 144)
  line L2 (-72, 144) -> (-22.3226, 74)
  line L3 (-22.3226, 74) -> (-18.3226, 74)
extrude "New 1'''''''''''''''''''''''''''''''''''''''''''''''''''''''''''''''''''''''''''''''''''''''''''''''''''''''''''''''" add sketch "New stock profile (112)" along normal blind 8 separate body makes body 254 in component "left ramp bridge forward"
ref_plane "WorkPlane1" through (0, -144, 0) normal (0, 1, 0) x (0, 0, 1) in component "right intake foundation cheek"
sketch "New stock profile (113)" plane through (0, -144, 0) normal (0, 1, 0) x (1, 0, 0) in component "right intake foundation cheek"
  line L0 (141.7, -98) -> (141.7, -120)
  line L1 (141.7, -120) -> (169, -120)
  line L2 (169, -120) -> (174, -138)
  line L3 (174, -138) -> (279, -115)
  line L4 (279, -115) -> (314.6, -114.8)
  line L5 (314.6, -114.8) -> (337, -114.8)
  line L6 (337, -114.8) -> (337, -64)
  line L7 (337, -64) -> (319, -44)
  line L8 (319, -44) -> (299, -44)
  line L9 (299, -44) -> (280, -54)
  line L10 (280, -54) -> (225, -54)
  line L11 (225, -54) -> (210, -74)
  line L12 (210, -74) -> (205, -90)
  line L13 (205, -90) -> (167, -106)
  line L14 (167, -106) -> (141.7, -98)
extrude "New 1''''''''''''''''''''''''''''''''''''''''''''''''''''''''''''''''''''''''''''''''''''''''''''''''''''''''''''''''" add sketch "New stock profile (113)" against normal blind 6 separate body makes body 255 in component "right intake foundation cheek"
ref_plane "WorkPlane1" through (214, 0, 0) normal (1, 0, 0) x (0, 1, 0) in component "right ramp bridge aft"
sketch "New stock profile (114)" plane through (214, 0, 0) normal (1, 0, 0) x (0, 0, -1) in component "right ramp bridge aft"
  line L0 (-44.6694, -74) -> (-19, -122)
  line L1 (-19, -122) -> (-19, -137)
  line L2 (-19, -137) -> (-67, -144)
  line L3 (-67, -144) -> (-82, -144)
  line L4 (-82, -144) -> (-28, -136)
  line L5 (-28, -136) -> (-28, -122)
  line L6 (-28, -122) -> (-48.6694, -74)
  line L7 (-48.6694, -74) -> (-44.6694, -74)
extrude "New 1'''''''''''''''''''''''''''''''''''''''''''''''''''''''''''''''''''''''''''''''''''''''''''''''''''''''''''''''''" add sketch "New stock profile (114)" along normal blind 8 separate body makes body 256 in component "right ramp bridge aft"
ref_plane "WorkPlane1" through (313, 0, 0) normal (1, 0, 0) x (0, 1, 0) in component "right ramp bridge forward"
sketch "New stock profile (115)" plane through (313, 0, 0) normal (1, 0, 0) x (0, 0, -1) in component "right ramp bridge forward"
  line L0 (-18.3226, -74) -> (-57, -144)
  line L1 (-57, -144) -> (-72, -144)
  line L2 (-72, -144) -> (-22.3226, -74)
  line L3 (-22.3226, -74) -> (-18.3226, -74)
extrude "New 1''''''''''''''''''''''''''''''''''''''''''''''''''''''''''''''''''''''''''''''''''''''''''''''''''''''''''''''''''" add sketch "New stock profile (115)" along normal blind 8 separate body makes body 257 in component "right ramp bridge forward"
component "left perimeter tube" placed x (0, 1, 0) y (0, 0, 1) z (1, 0, 0) at (-340, 327.3, 89.4)
component "left front return" placed x (-1, 0, 0) y (0, 0, 1) z (0, 1, 0) at (327.3, 150, 89.4)
component "left red side bumper" placed x (1, 0, 0) y (0, 1, 0) z (0, 0, 1) at (0, 378, 48)
component "left red front bumper" placed x (1, 0, 0) y (0, 1, 0) z (0, 0, 1) at (378, 245, 48)
component "right perimeter tube" placed x (0, 1, 0) y (0, 0, 1) z (1, 0, 0) at (-340, -327.3, 89.4)
component "right front return" placed x (-1, 0, 0) y (0, 0, 1) z (0, 1, 0) at (327.3, -314.6, 89.4)
component "right red side bumper" placed x (1, 0, 0) y (0, 1, 0) z (0, 0, 1) at (0, -378, 48)
component "right red front bumper" placed x (1, 0, 0) y (0, 1, 0) z (0, 0, 1) at (378, -245, 48)
component "rear perimeter tube" placed x (-1, 0, 0) y (0, 0, 1) z (0, 1, 0) at (-327.3, -314.6, 89.4)
component "rear red bumper" placed x (1, 0, 0) y (0, 1, 0) z (0, 0, 1) at (-378, 0, 48)
component "front left module tab spacer 1" placed x (1, 0, 0) y (0, 1, 0) z (0, 0, 1) at (198, 303.05, 78.32)
component "front left module tab spacer 2" placed x (1, 0, 0) y (0, 1, 0) z (0, 0, 1) at (303.05, 198, 78.32)
component "front right module tab spacer 1" placed x (1, 0, 0) y (0, 1, 0) z (0, 0, 1) at (303.05, -198, 78.32)
component "front right module tab spacer 2" placed x (1, 0, 0) y (0, 1, 0) z (0, 0, 1) at (198, -303.05, 78.32)
component "rear left module tab spacer 1" placed x (1, 0, 0) y (0, 1, 0) z (0, 0, 1) at (-303.05, 198, 78.32)
component "rear left module tab spacer 2" placed x (1, 0, 0) y (0, 1, 0) z (0, 0, 1) at (-198, 303.05, 78.32)
component "rear right module tab spacer 1" placed x (1, 0, 0) y (0, 1, 0) z (0, 0, 1) at (-198, -303.05, 78.32)
component "rear right module tab spacer 2" placed x (1, 0, 0) y (0, 1, 0) z (0, 0, 1) at (-303.05, -198, 78.32)
component "rear right hopper post" placed x (1, 0, 0) y (0, 1, 0) z (0, 0, 1) at (-188, -306, 115)
component "front right hopper post" placed x (1, 0, 0) y (0, 1, 0) z (0, 0, 1) at (176, -306, 115)
component "right floor sill" placed x (0, 1, 0) y (0, 0, 1) z (1, 0, 0) at (-330, -306, 227)
component "rear left hopper post" placed x (1, 0, 0) y (0, 1, 0) z (0, 0, 1) at (-188, 306, 115)
component "front left hopper post" placed x (1, 0, 0) y (0, 1, 0) z (0, 0, 1) at (176, 306, 115)
component "left floor sill" placed x (0, 1, 0) y (0, 0, 1) z (1, 0, 0) at (-330, 306, 227)